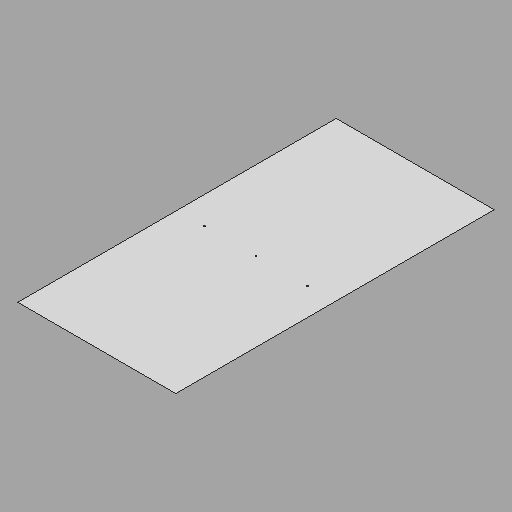
# Autodesk Inventor part: 2nd_EVA
Saved by Autodesk Inventor 2026.2 (Build 302298000, 298)
## iProperties
Created: 2026-09-16
Part Number: 2nd_EVA
Material: Polytetrafluoroethylene
Document SubType Name: Modeling
Designer: Jacob
Density: 2.02 g/cm^3
Appearance: Clear
EVA2_Thickness: 0.450 mm
Author: Jacob
Autodesk Inventor part; units mm, degrees
ref_plane "YZ Plane" through (0, 0, 0) normal (1, 0, 0) x (0, 1, 0)
ref_plane "XZ Plane" through (0, 0, 0) normal (0, 1, 0) x (-1, 0, 0)
ref_plane "XY Plane" through (0, 0, 0) normal (0, 0, 1) x (1, 0, 0)
sketch "Sketch1" plane through (0, 0, 0) normal (0, 1, 0) x (-1, 0, 0)
  line L0 (-564, 1136.5) -> (564, 1136.5)
  line L1 (564, 1136.5) -> (564, -1136.5)
  line L2 (564, -1136.5) -> (-564, -1136.5)
  line L3 (-564, -1136.5) -> (-564, 1136.5)
  line L4 (-564, 1136.5) -> (564, -1136.5) construction
  line L5 (564, 1136.5) -> (-564, -1136.5) construction
  circle A0 centre (-367.6, 0) radius 6
  circle A1 centre (0, 0) radius 6
  circle A2 centre (367.6, 0) radius 6
  point P0 (0, 0)
  dimension "d0" = 1128
  dimension "d1" = 2273
  dimension "d4" = 12
  dimension "d5" = 12
  dimension "d6" = 12
  dimension "d7" = 367.6
  dimension "d9" = 367.6
  dimension "d10" = 196.4
  dimension "d11" = 1136.5
  constraints: 12 end point, 3 centre point, 2 horizontal alignment, 2 midpoint, 2 parallel, 1 horizontal, 1 perpendicular
  measures "d0" distance of L1.end L2.end
  measures "d1" distance of L0.end L1.end
  measures "d4" diameter of A0
  measures "d5" diameter of A1
  measures "d6" diameter of A2
  measures "d7" distance of A1.centre A0.centre
  measures "d9" distance of A2.centre A1.centre
  measures "d10" distance from line of L1 A2.centre
  measures "d11" distance from line of L0 A1.centre
extrude "Extrusion2" add sketch "Sketch1" along normal blind 0.45
equation "\"d12\" = EVA2_Thickness"
equation "\"EVA2_Thickness\" = 0.45"
body "Solid2"
